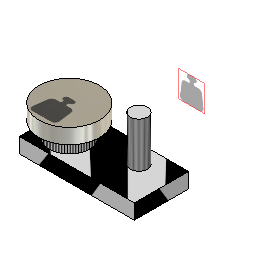
A v3 (Autodesk Fusion 360 archive; units mm, degrees)
design "C"
Autodesk Fusion 360 part; units mm, degrees
box "直方体プリミティブ1" add length 36.1328 width 76.4579 height -10 placed x (0, 1, 0) y (-1, 0, 0) z (0, 0, 1) at (46.4579, -60, 0) makes body 1
cylinder "円柱プリミティブ1" add diameter 26.8 height 10 placed x (1, 0, 0) y (0, 1, 0) z (0, 0, 1) at (-12.7926, -43.9895, 0) bodies 1
sketch "スケッチ3" plane through (0, 0, 0) normal (0, 0, 1) x (-1, 0, 0)
  circle A0 centre (12.7926, 43.9895) radius 13.4
  line L0 (30, 60) -> (-46.4579, 60)
  line L1 (-46.4579, 60) -> (-46.4579, 23.8672)
  line L2 (-46.4579, 23.8672) -> (30, 23.8672)
  line L3 (30, 23.8672) -> (30, 60)
  circle A1 centre (-25.6764, 36.2104) radius 5.7493
extrude "押し出し1" add sketch "スケッチ3" along normal blind 30 contours A1 bodies 1
cylinder "円柱プリミティブ1'" add diameter 40 height 10 placed x (1, 0, 0) y (0, 1, 0) z (0, 0, 1) at (60, 50, 0) separate body makes body 2 in component "Component"
ref_plane "作業平面1" through (56.4579, -41.9336, -5) normal (1, 0, 0) x (0, 0, 1)
component "Component" placed x (1, 0, 0) y (0, 1, 0) z (0, 0, 1) at (-72.7926, -93.9895, 10)
